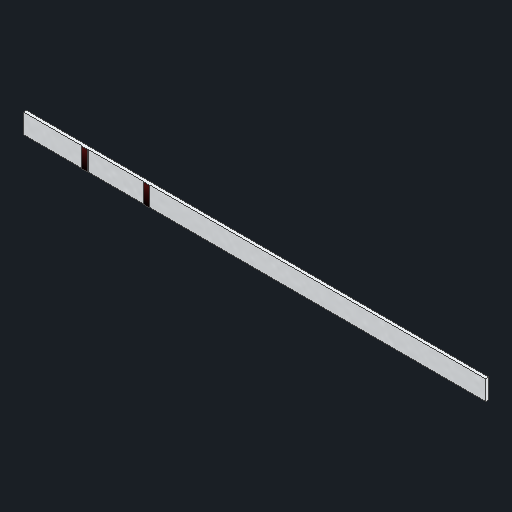
# Autodesk Inventor part: LFA Strip (bare)
Saved by Autodesk Inventor 2027.2 (Build 312334000, 334)
## iProperties
Created: 2026-11-11
Part Number: LFA Strip (bare)
Material: Generic
Description: Bare LFA strip, 75 x 3.175 mm; C line 10 mm and T line 20 mm from the testing end, 1 mm wide; thickness assumed 0.5 mm
Document SubType Name: Modeling
Designer: isaac
Density: 1 g/cm^3
Appearance: Default
Author: isaac
Autodesk Inventor part; units mm, degrees
ref_plane "YZ Plane" through (0, 0, 0) normal (1, 0, 0) x (0, 1, 0)
sketch "Sketch1" plane through (0, 0, 0) normal (0, 0, 1) x (1, 0, 0)
  line L0 (0, -1.5875) -> (75, -1.5875)
  line L1 (75, -1.5875) -> (75, 1.5875)
  line L2 (75, 1.5875) -> (0, 1.5875)
  line L3 (0, 1.5875) -> (0, -1.5875)
  constraints: 8 end point, 2 parallel, 1 horizontal, 1 perpendicular
extrude "Strip" add sketch "Sketch1" along normal blind 0.5
ref_plane "Work Plane1" through (0, 0, 0.5) normal (0, 0, 1) x (1, 0, 0)
sketch "Sketch2" plane through (0, 0, 0.5) normal (0, 0, 1) x (1, 0, 0)
  line L0 (9.5, -1.5875) -> (10.5, -1.5875)
  line L1 (10.5, -1.5875) -> (10.5, 1.5875)
  line L2 (10.5, 1.5875) -> (9.5, 1.5875)
  line L3 (9.5, 1.5875) -> (9.5, -1.5875)
  constraints: 8 end point, 2 parallel, 1 horizontal, 1 perpendicular
extrude "C line" add sketch "Sketch2" along normal blind 0.05
ref_plane "Work Plane2" through (0, 0, 0.5) normal (0, 0, 1) x (1, 0, 0)
sketch "Sketch3" plane through (0, 0, 0.5) normal (0, 0, 1) x (1, 0, 0)
  line L0 (19.5, -1.5875) -> (20.5, -1.5875)
  line L1 (20.5, -1.5875) -> (20.5, 1.5875)
  line L2 (20.5, 1.5875) -> (19.5, 1.5875)
  line L3 (19.5, 1.5875) -> (19.5, -1.5875)
  constraints: 8 end point, 2 parallel, 1 horizontal, 1 perpendicular
extrude "T line" add sketch "Sketch3" along normal blind 0.05
body "Solid1"
